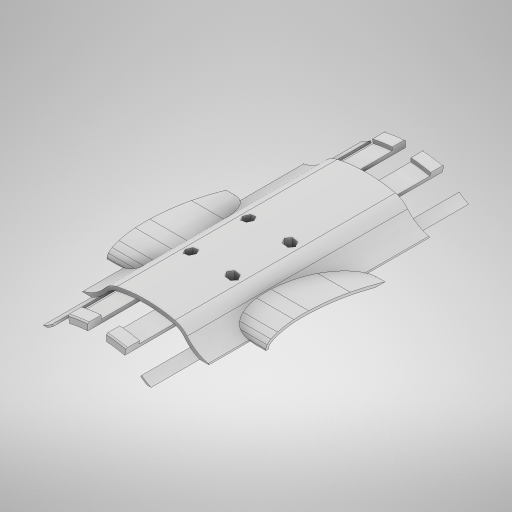
# Autodesk Inventor part: ENCASTRE_FUSELAJE
Saved by Autodesk Inventor 2023 (Build 270158000, 158)
## iProperties
Created: 2023-05-19
Part Number: ENCASTRE_FUSELAJE
Material: Genérico
Document SubType Name: Modeling
Designer: brand
Density: 1 g/cm^3
Appearance: Valor por defecto
Author: brand
Autodesk Inventor part; units mm, degrees
ref_plane "XZ Plane" through (0, 0, 0) normal (0, 1, 0) x (-1, 0, 0)
ref_plane "XY Plane" through (0, 0, 0) normal (0, 0, 1) x (1, 0, 0)
sketch "Boceto1" plane through (0, 0, 0) normal (0, 0, 1) x (1, 0, 0)
  line L0 (-27.5, 0) -> (27.5, 0) construction
  arc A0 (33, 24.3875) -> (-33, 24.3875) centre (0, -121.9375) ccw
  arc A1 (-33, -24.3875) -> (33, -24.3875) centre (0, 121.9375) ccw
  arc A2 (-70.9258, 0.9771) -> (-46.9085, 15.7579) centre (-80, 42.625) ccw
  arc A3 (-46.9085, -15.7579) -> (-70.9258, -0.9771) centre (-80, -42.625) ccw
  line L1 (0, 28.0625) -> (0, -28.0625) construction
  arc A4 (46.9085, 15.7579) -> (70.9258, 0.9771) centre (80, 42.625) ccw
  arc A5 (70.9258, -0.9771) -> (46.9085, -15.7579) centre (80, -42.625) ccw
  arc A6 (-33, 24.3875) -> (-46.9085, 15.7579) centre (-27.5, 0) ccw
  arc A7 (-46.9085, -15.7579) -> (-33, -24.3875) centre (-27.5, 0) ccw
  arc A8 (33, -24.3875) -> (46.9085, -15.7579) centre (27.5, 0) ccw
  arc A9 (46.9085, 15.7579) -> (33, 24.3875) centre (27.5, 0) ccw
  arc A10 (32.12, 20.4855) -> (-32.12, 20.4855) centre (0, -121.9375) ccw
  arc A11 (43.8031, 13.2366) -> (32.12, 20.4855) centre (27.5, 0) ccw
  arc A12 (43.8031, 13.2366) -> (61.1056, 0) centre (80, 42.625) ccw
  arc A13 (61.1056, 0) -> (43.8031, -13.2366) centre (80, -42.625) ccw
  arc A14 (32.12, -20.4855) -> (43.8031, -13.2366) centre (27.5, 0) ccw
  arc A15 (-32.12, -20.4855) -> (32.12, -20.4855) centre (0, 121.9375) ccw
  arc A16 (-43.8031, -13.2366) -> (-32.12, -20.4855) centre (-27.5, 0) ccw
  arc A17 (-43.8031, -13.2366) -> (-61.1056, 0) centre (-80, -42.625) ccw
  arc A18 (-61.1056, 0) -> (-43.8031, 13.2366) centre (-80, 42.625) ccw
  arc A19 (-32.12, 20.4855) -> (-43.8031, 13.2366) centre (-27.5, 0) ccw
  arc A20 (-70.9258, 0.9771) -> (-70.9258, -0.9771) centre (-70.7129, 0) ccw
  arc A21 (70.9258, -0.9771) -> (70.9258, 0.9771) centre (70.7129, 0) ccw
  point P0 (0, 0)
  point P1 (0, 0)
  point P2 (0, 0)
  dimension "d0" = 300
  dimension "d1" = 55
  dimension "d2" = 80
  dimension "d3" = 80
  dimension "d4" = 4
  dimension "d5" = 1
  constraints: 46 point on circle, 22 centre point, 6 tangent, 5 symmetric about line, 4 end point, 2 horizontal alignment, 1 coincident, 1 equal radius, 1 horizontal, 1 midpoint, 9 other
  measures "d0" diameter of A0
  measures "d1" distance of L0.start L0.end
  measures "d2" horizontal distance of point (0, 0) A18.centre
  measures "d3" horizontal distance of point (0, 0) A17.centre
  measures "d4" radial gap between concentric circles of A0 A10
  measures "d5" radius of A20
extrude "Extrusión1" add sketch "Boceto1" against normal blind 170
sketch "Boceto2" plane through (0, 0, 0) normal (1, 0, 0) x (0, 1, 0)
  arc A0 (-6.4315, -149.3718) -> (5.8247, -101.1329) centre (-420.6839, -18.445) ccw
  arc A1 (5.8247, -101.1329) -> (11.1529, -54.4749) centre (-297.3284, -42.881) ccw
  arc A2 (11.1529, -54.4749) -> (10.9145, -38.2426) centre (-144.1615, -48.6381) ccw
  arc A3 (10.9145, -38.2426) -> (7.8362, -20.5745) centre (-74.6379, -44.046) ccw
  arc A4 (7.8362, -20.5745) -> (5.0303, -13.6138) centre (-27.6939, -30.851) ccw
  arc A5 (5.0303, -13.6138) -> (2.575, -10.4857) centre (-4.0493, -18.2127) ccw
  arc A6 (2.575, -10.4857) -> (1.0803, -9.8637) centre (0.7767, -12.7005) ccw
  arc A7 (1.0803, -9.8637) -> (0.0741, -10.1303) centre (1.0883, -11.9261) ccw
  arc A8 (0.0741, -10.1303) -> (-1.6628, -12.1788) centre (2.0349, -13.5535) ccw
  arc A9 (-1.6628, -12.1788) -> (-2.3399, -14.3359) centre (17.2896, -19.3122) ccw
  arc A10 (-2.3399, -14.3359) -> (-3.2686, -18.7673) centre (27.4031, -22.8823) ccw
  arc A11 (-3.2686, -18.7673) -> (-3.7812, -23.8522) centre (82.0127, -29.9326) ccw
  arc A12 (-3.7812, -23.8522) -> (-4.3081, -39.7592) centre (210.5666, -38.9149) ccw
  line L0 (-4.3081, -39.7592) -> (-4.2703, -45.447)
  line L1 (-4.2703, -45.447) -> (-4.0474, -59.6695)
  arc A13 (-4.2226, -74.4673) -> (-4.0474, -59.6695) centre (-320.6036, -63.321) ccw
  arc A14 (-4.9188, -90.3853) -> (-4.2226, -74.4673) centre (-890.267, -43.6885) ccw
  line L2 (-4.9188, -90.3853) -> (-5.6302, -104.0213)
  arc A15 (-5.6302, -104.0213) -> (-6.0563, -116.5268) centre (482.8669, -126.9256) ccw
  arc A16 (-6.0563, -116.5268) -> (-6.3146, -149.378) centre (962.6143, -140.5688) ccw
  line L3 (-6.3146, -149.378) -> (-6.4315, -149.3718)
  line L4 (0, 0) -> (0, -170) projected
  arc A17 (-4.5792, -23.7958) -> (-5.1081, -39.7634) centre (210.5666, -38.9149) ccw
  arc A18 (-4.0616, -18.6622) -> (-4.5792, -23.7958) centre (82.0127, -29.9326) ccw
  arc A19 (-3.1122, -14.127) -> (-4.0616, -18.6622) centre (27.4031, -22.8823) ccw
  arc A20 (-2.4121, -11.8984) -> (-3.1122, -14.127) centre (17.2896, -19.3122) ccw
  arc A21 (-0.3215, -9.435) -> (-2.4121, -11.8984) centre (2.0349, -13.5535) ccw
  arc A22 (1.1223, -9.0639) -> (-0.3215, -9.435) centre (1.0883, -11.9261) ccw
  arc A23 (3.0879, -9.8716) -> (1.1223, -9.0639) centre (0.7767, -12.7005) ccw
  arc A24 (5.741, -13.2466) -> (3.0879, -9.8716) centre (-4.0493, -18.2127) ccw
  arc A25 (8.6051, -20.3539) -> (5.741, -13.2466) centre (-27.6939, -30.851) ccw
  arc A26 (11.7126, -38.1888) -> (8.6051, -20.3539) centre (-74.6379, -44.046) ccw
  arc A27 (11.9522, -54.5073) -> (11.7126, -38.1888) centre (-144.1615, -48.6381) ccw
  arc A28 (6.6102, -101.2845) -> (11.9522, -54.5073) centre (-297.3284, -42.881) ccw
  arc A29 (-5.8557, -150.2031) -> (6.6102, -101.2845) centre (-420.6839, -18.445) ccw
  line L5 (-5.8557, -150.2031) -> (-7.1074, -150.1375)
  arc A30 (-6.8561, -116.5083) -> (-7.1074, -150.1375) centre (962.6143, -140.5688) ccw
  arc A31 (-6.4292, -103.9817) -> (-6.8561, -116.5083) centre (482.8669, -126.9256) ccw
  line L6 (-6.4292, -103.9817) -> (-5.7177, -90.3434)
  arc A32 (-5.7177, -90.3434) -> (-5.0221, -74.4394) centre (-890.267, -43.6885) ccw
  arc A33 (-5.0221, -74.4394) -> (-4.8473, -59.6804) centre (-320.6036, -63.321) ccw
  line L7 (-4.8473, -59.6804) -> (-5.0703, -45.4559)
  line L8 (-5.0703, -45.4559) -> (-5.1081, -39.7634)
  line L9 (1.1223, -9.0639) -> (-24.0625, -9.0639) construction
  line L10 (-24.0625, -170) -> (-24.0625, 0) projected
  line L11 (-5.9636, -150.0472) -> (-24.0625, -150.0472) construction
  circle A34 centre (-336.4534, -54.4805) radius 340 construction
  line L12 (-24.0625, -6.0639) -> (24.3875, -6.0639)
  line L13 (24.3875, 0) -> (24.3875, -170) projected
  line L14 (-24.0625, -153.0472) -> (24.3875, -153.0472)
  circle A35 centre (1.7519, -16.7828) radius 2.25
  circle A36 centre (3.3626, -54.9049) radius 4.25
  circle A37 centre (-1.8171, -114.7492) radius 2.25
  point P0 (0, -10)
  dimension "d8" = 10
  dimension "d9" = 0.8
  dimension "d11" = 680
  dimension "d12" = 336.4534
  dimension "d13" = 54.4805
  dimension "d14" = 3
  dimension "d15" = 3
  dimension "d16" = 150.0472
  dimension "d19" = 4.5
  dimension "d20" = 8.5
  dimension "d21" = 4.5
  dimension "d22" = 16.7828
  dimension "d23" = 1.7519
  dimension "d24" = 54.9049
  dimension "d25" = 3.3626
  dimension "d26" = 114.7492
  dimension "d27" = 1.8171
  constraints: 68 point on circle, 38 centre point, 24 end point, 6 point on line, 3 horizontal, 1 perpendicular, 20 other
  measures "d8" distance of L4.start point (0, -10)
  measures "d9" radial gap between concentric circles of A12 A17
  measures "d11" diameter of A34
  measures "d12" horizontal distance of A34.centre L4.start
  measures "d13" vertical distance of A34.centre L4.start
  measures "d14" distance between parallel lines of L12 L9
  measures "d15" distance between parallel lines of L14 L11
  measures "d16" distance from line of L11 L4.start
  measures "d19" diameter of A35
  measures "d20" diameter of A36
  measures "d21" diameter of A37
  measures "d22" vertical distance of A35.centre L4.start
  measures "d23" horizontal distance of A35.centre L4.start
  measures "d24" vertical distance of A36.centre L4.start
  measures "d25" horizontal distance of A36.centre L4.start
  measures "d26" vertical distance of A37.centre L4.start
  measures "d27" horizontal distance of A37.centre L4.start
extrude "Extrusión2" add sketch "Boceto2" along normal mid plane 13 contours A29 A28 A27 A26 A25 A24 A23 A22 L4 L12 L13 L14 | L4 L14 L10 L12 A22 A21 A20 A19 A18 A17 L8 L7 A33 A32 L6 A31 A30 L5 A29
sketch "Boceto3" plane through (6.5, 0, 0) normal (1, 0, 0) x (0, 0, -1)
  line L0 (153.0472, 23.9178) -> (6.0639, 23.9178) projected
  line L1 (6.0639, -23.9178) -> (153.0472, -23.9178) projected
  line L2 (6.0639, -23.9178) -> (6.0639, 23.9178) projected
  line L3 (153.0472, 23.9178) -> (153.0472, -23.9178) projected
  circle A0 centre (16.783, 1.752) radius 4
  circle A1 centre (54.905, 3.363) radius 5.25
  circle A2 centre (114.749, -1.817) radius 4
  point P0 (0, 0)
  dimension "d28" = 8
  dimension "d29" = 10.5
  dimension "d30" = 8
  dimension "d31" = 16.783
  dimension "d32" = 1.752
  dimension "d33" = 3.363
  dimension "d34" = 54.905
  dimension "d35" = 114.749
  dimension "d36" = 1.817
  constraints: 3 centre point
  measures "d28" diameter of A0
  measures "d29" diameter of A1
  measures "d30" diameter of A2
  measures "d31" horizontal distance of point (0, 0) A0.centre
  measures "d32" vertical distance of point (0, 0) A0.centre
  measures "d33" vertical distance of point (0, 0) A1.centre
  measures "d34" horizontal distance of point (0, 0) A1.centre
  measures "d35" horizontal distance of point (0, 0) A2.centre
  measures "d36" vertical distance of point (0, 0) A2.centre
extrude "Extrusión3" add sketch "Boceto3" along normal blind 4
mirror "Simetría1" about plane through (0, 0, 0) normal (1, 0, 0) of "Extrusión3"
sketch "Boceto4" plane through (0, 0, 0) normal (1, 0, 0) x (0, 1, 0)
  circle A0 centre (1.752, -16.783) radius 4 projected
  circle A1 centre (3.363, -54.905) radius 5.25 projected
  circle A2 centre (-1.817, -114.749) radius 4 projected
  point P0 (0, 0)
extrude "Extrusión4" cut sketch "Boceto4" along normal through all both and the other way through all
sketch "Boceto5" plane through (0, 0, 0) normal (0, 1, 0) x (-1, 0, 0)
  circle A0 centre (-23.62, -99.8876) radius 8.5
  line L0 (32.12, -170) -> (-32.12, -170) projected
  line L1 (-33, -170) -> (33, -170) projected
  line L2 (0, -170) -> (0, 0)
  line L3 (10.5, -153.0472) -> (-10.5, -153.0472) projected
  line L4 (-10.5, -153.0472) -> (-10.5, -6.0639) projected
  line L5 (-10.5, -6.0639) -> (10.5, -6.0639) projected
  line L6 (10.5, -6.0639) -> (10.5, -153.0472) projected
  line L7 (-32.12, 0) -> (32.12, 0) projected
  line L8 (-32.12, 0) -> (-32.12, -170) projected
  line L9 (32.12, -170) -> (-32.12, -170) projected
  line L10 (32.12, 0) -> (32.12, -170) projected
  circle A1 centre (-23.62, -34.8116) radius 8.5
  circle A2 centre (23.62, -99.8876) radius 8.5
  circle A3 centre (23.62, -34.8116) radius 8.5
  circle A4 centre (-23.62, -99.8876) radius 3.25
  circle A5 centre (-23.62, -34.8116) radius 3.25
  circle A6 centre (23.62, -99.8876) radius 3.25
  circle A7 centre (23.62, -34.8116) radius 3.25
  dimension "d41" = 17
  dimension "d42" = 6.5
  dimension "d43" = 6.5
  constraints: 8 centre point, 4 symmetric about line, 2 coincident, 2 end point, 2 tangent, 1 equal radius, 1 midpoint, 1 vertical, 4 other
  measures "d41" diameter of A0
  measures "d42" diameter of A4
  measures "d43" diameter of A5
extrude "Extrusión5" add sketch "Boceto5" along normal mid plane 20 contours A0 | A1 | A2 | A3
sketch "Boceto6" plane through (23.62, 10, -34.8116) normal (0, 1, 0) x (1, 0, 0)
  circle A0 centre (0, 0) radius 3.25 projected
  line L0 (-3.1754, 5.5) -> (3.1754, 5.5)
  line L1 (3.1754, 5.5) -> (6.3509, 0)
  line L2 (6.3509, 0) -> (3.1754, -5.5)
  line L3 (3.1754, -5.5) -> (-3.1754, -5.5)
  line L4 (-3.1754, -5.5) -> (-6.3509, 0)
  line L5 (-6.3509, 0) -> (-3.1754, 5.5)
  circle A1 centre (0, 0) radius 10.5
  line L6 (-23.62, -34.8116) -> (-23.62, 135.1884)
  line L7 (9.38, 135.1884) -> (-56.62, 135.1884) projected
  circle A2 centre (0, 65.076) radius 3.25 projected
  line L8 (0, 65.076) -> (0, 0)
  line L9 (0, 32.538) -> (-50.0066, 32.538)
  circle A3 centre (0, 65.076) radius 3.25
  line L10 (-3.1754, 59.576) -> (3.1754, 59.576)
  line L11 (3.1754, 59.576) -> (6.3509, 65.076)
  line L12 (6.3509, 65.076) -> (3.1754, 70.576)
  line L13 (3.1754, 70.576) -> (-3.1754, 70.576)
  line L14 (-3.1754, 70.576) -> (-6.3509, 65.076)
  line L15 (-6.3509, 65.076) -> (-3.1754, 59.576)
  circle A4 centre (0, 65.076) radius 10.5
  circle A5 centre (-47.24, 0) radius 3.25
  line L16 (-44.0646, 5.5) -> (-50.4154, 5.5)
  line L17 (-50.4154, 5.5) -> (-53.5909, 0)
  line L18 (-53.5909, 0) -> (-50.4154, -5.5)
  line L19 (-50.4154, -5.5) -> (-44.0646, -5.5)
  line L20 (-44.0646, -5.5) -> (-40.8891, 0)
  line L21 (-40.8891, 0) -> (-44.0646, 5.5)
  circle A6 centre (-47.24, 0) radius 10.5
  circle A7 centre (-47.24, 65.076) radius 3.25
  line L22 (-47.24, 65.076) -> (-47.24, 0)
  line L23 (-50.4154, 59.576) -> (-53.5909, 65.076)
  line L24 (-40.8891, 65.076) -> (-44.0646, 59.576)
  circle A8 centre (-47.24, 65.076) radius 3.25
  line L25 (-53.5909, 65.076) -> (-50.4154, 70.576)
  line L26 (-50.4154, 70.576) -> (-44.0646, 70.576)
  line L27 (-44.0646, 70.576) -> (-40.8891, 65.076)
  circle A9 centre (-47.24, 65.076) radius 10.5
  line L28 (-44.0646, 59.576) -> (-50.4154, 59.576)
  point P0 (0, 5.5)
  point P1 (0, 59.576)
  point P2 (-47.24, 5.5)
  point P3 (-47.24, 32.538)
  point P4 (-47.24, 59.576)
  dimension "d46" = 11
  dimension "d47" = 11
  dimension "d48" = 11
  dimension "d49" = 120
  dimension "d50" = 120
  dimension "d51" = 21
  constraints: 56 end point, 27 symmetric about line, 8 centre point, 4 coincident, 3 midpoint, 3 parallel, 2 horizontal, 1 equal length, 1 horizontal alignment, 1 vertical, 1 vertical alignment, 7 other
  measures "d46" distance between parallel lines of L3 L0
  measures "d47" distance between parallel lines of L4 L1
  measures "d48" distance between parallel lines of L5 L2
  measures "d49" angle of L5 L0
  measures "d50" angle of L2 L1
  measures "d51" diameter of A1
extrude "Extrusión6" add sketch "Boceto6" along normal through all contours A1 | A4 | A6 | A9
sketch "Boceto7" plane through (-23.62, 10, -34.8116) normal (0, -1, 0) x (1, 0, 0)
  line L0 (-6.3509, 0) -> (-3.1754, -5.5) projected
  line L1 (-3.1754, -5.5) -> (3.1754, -5.5) projected
  line L2 (3.1754, -5.5) -> (6.3509, 0) projected
  line L3 (6.3509, 0) -> (3.1754, 5.5) projected
  line L4 (3.1754, 5.5) -> (-3.1754, 5.5) projected
  line L5 (-3.1754, 5.5) -> (-6.3509, 0) projected
  line L6 (40.8891, 0) -> (44.0646, -5.5) projected
  line L7 (44.0646, -5.5) -> (50.4154, -5.5) projected
  line L8 (50.4154, -5.5) -> (53.5909, 0) projected
  line L9 (53.5909, 0) -> (50.4154, 5.5) projected
  line L10 (50.4154, 5.5) -> (44.0646, 5.5) projected
  line L11 (44.0646, 5.5) -> (40.8891, 0) projected
  line L12 (53.5909, -65.076) -> (50.4154, -59.576) projected
  line L13 (50.4154, -59.576) -> (44.0646, -59.576) projected
  line L14 (44.0646, -59.576) -> (40.8891, -65.076) projected
  line L15 (40.8891, -65.076) -> (44.0646, -70.576) projected
  line L16 (44.0646, -70.576) -> (50.4154, -70.576) projected
  line L17 (50.4154, -70.576) -> (53.5909, -65.076) projected
  line L18 (6.3509, -65.076) -> (3.1754, -59.576) projected
  line L19 (3.1754, -59.576) -> (-3.1754, -59.576) projected
  line L20 (-3.1754, -59.576) -> (-6.3509, -65.076) projected
  line L21 (-6.3509, -65.076) -> (-3.1754, -70.576) projected
  line L22 (-3.1754, -70.576) -> (3.1754, -70.576) projected
  line L23 (3.1754, -70.576) -> (6.3509, -65.076) projected
  point P0 (23.62, 34.8116)
extrude "Extrusión7" cut sketch "Boceto7" against normal through all
sketch "Boceto8" plane through (-23.62, -10, -34.8116) normal (0, -1, 0) x (1, 0, 0)
  circle A0 centre (0, 0) radius 10.5 projected
  circle A1 centre (0, 0) radius 8.5 projected
  circle A2 centre (47.24, 0) radius 10.5 projected
  circle A3 centre (47.24, 0) radius 8.5 projected
  circle A4 centre (47.24, -65.076) radius 10.5 projected
  circle A5 centre (47.24, -65.076) radius 8.5 projected
  circle A6 centre (0, -65.076) radius 10.5 projected
  circle A7 centre (0, -65.076) radius 8.5 projected
  point P0 (23.62, 34.8116)
extrude "Extrusión8" add sketch "Boceto8" against normal blind 5
sketch "Boceto9" plane through (-23.62, -10, -34.8116) normal (0, -1, 0) x (1, 0, 0)
  circle A0 centre (0, 0) radius 8.5 projected
  circle A1 centre (47.24, 0) radius 8.5 projected
  circle A2 centre (47.24, -65.076) radius 8.5 projected
  circle A3 centre (0, -65.076) radius 8.5 projected
  point P0 (23.62, 34.8116)
extrude "Extrusión9" cut sketch "Boceto9" along normal through all
sketch "Boceto10" plane through (-23.62, -10, -34.8116) normal (0, -1, 0) x (1, 0, 0)
  circle A0 centre (0, 0) radius 10.5 projected
  circle A1 centre (47.24, 0) radius 10.5 projected
  circle A2 centre (0, -65.076) radius 10.5 projected
  circle A3 centre (47.24, -65.076) radius 10.5 projected
  circle A4 centre (0, 0) radius 8.5 projected
  circle A5 centre (47.24, 0) radius 10.5 projected
  circle A6 centre (47.24, 0) radius 8.5 projected
  circle A7 centre (47.24, -65.076) radius 10.5 projected
  circle A8 centre (47.24, -65.076) radius 8.5 projected
  circle A9 centre (0, -65.076) radius 10.5 projected
  circle A10 centre (0, -65.076) radius 8.5 projected
  point P0 (23.62, 34.8116)
extrude "Extrusión10" add sketch "Boceto10" along normal through all
sketch "Boceto11" plane through (0, 0, 0) normal (0, 0, 1) x (1, 0, 0)
  arc A0 (10.5, 23.6845) -> (-10.5, 23.6845) centre (0, -121.9375) ccw projected
  line L0 (-10.5, 23.6845) -> (-10.5, -23.6845) projected
  arc A1 (-10.5, -23.6845) -> (10.5, -23.6845) centre (0, 121.9375) ccw projected
  line L1 (10.5, 23.6845) -> (10.5, -23.6845) projected
  line L2 (-10.5, 0) -> (-77.0735, 0)
  line L3 (-15.12, -5) -> (-15.12, 10) projected
  line L4 (-77.0735, 0) -> (-77.0735, -40.4156)
  line L5 (-77.0735, -40.4156) -> (86.7734, -40.4156)
  line L6 (86.7734, -40.4156) -> (86.7734, 0)
  line L7 (86.7734, 0) -> (10.5, 0)
  line L8 (10.5, -23.6845) -> (10.5, 23.6845) projected
  point P0 (0, 0)
  point P1 (10.5, 0)
  constraints: 10 end point, 4 perpendicular, 2 midpoint, 1 point on line
extrude "Extrusión11" cut sketch "Boceto11" against normal through all contours L7 L6 L5 L4 L2 L0 A1 L1
sketch "Boceto12" plane through (10.5, 0, 0) normal (1, 0, 0) x (0, 0, -1)
  circle A0 centre (54.481, -336.453) radius 340
  point P0 (0, 0)
  dimension "d64" = 680
  dimension "d65" = 336.453
  dimension "d66" = 54.481
  constraints: 1 centre point
  measures "d64" diameter of A0
  measures "d65" vertical distance of point (0, 0) A0.centre
  measures "d66" horizontal distance of point (0, 0) A0.centre
extrude "Extrusión12" cut sketch "Boceto12" against normal up to surface (21 mm away)
ref_plane "Plano de trabajo1" through (90, 0, 0) normal (1, 0, 0) x (0, 1, 0)
sketch "Boceto13" plane through (90, 0, 0) normal (1, 0, 0) x (0, 1, 0)
  arc A0 (3.5128, -49.6571) -> (1.8728, -20.7812) centre (-336.453, -54.481) ccw projected
  arc A1 (3.4997, -60.1532) -> (3.5128, -49.6571) centre (3.363, -54.905) ccw projected
  arc A2 (-1.1507, -110.8049) -> (3.4997, -60.1532) centre (-336.453, -54.481) ccw projected
  arc A3 (-2.5686, -118.6777) -> (-1.1507, -110.8049) centre (-1.817, -114.749) ccw projected
  arc A4 (-7.1535, -139.1087) -> (-2.5686, -118.6777) centre (-336.453, -54.481) ccw projected
  arc A5 (-7.1535, -139.1087) -> (-7.1074, -150.1375) centre (962.6143, -140.5688) ccw projected
  line L0 (-7.1074, -150.1375) -> (-5.8557, -150.2031) projected
  arc A6 (-5.8557, -150.2031) -> (6.6102, -101.2845) centre (-420.6839, -18.445) ccw projected
  arc A7 (6.6102, -101.2845) -> (11.9522, -54.5073) centre (-297.3284, -42.881) ccw projected
  arc A8 (11.9522, -54.5073) -> (11.7126, -38.1888) centre (-144.1615, -48.6381) ccw projected
  arc A9 (11.7126, -38.1888) -> (8.6051, -20.3539) centre (-74.6379, -44.046) ccw projected
  arc A10 (8.6051, -20.3539) -> (5.741, -13.2466) centre (-27.6939, -30.851) ccw projected
  arc A11 (5.741, -13.2466) -> (3.0879, -9.8716) centre (-4.0493, -18.2127) ccw projected
  arc A12 (3.0879, -9.8716) -> (1.1223, -9.0639) centre (0.7767, -12.7005) ccw projected
  arc A13 (1.1223, -9.0639) -> (0.5079, -9.1232) centre (1.0883, -11.9261) ccw projected
  arc A14 (0.9894, -12.8564) -> (0.5079, -9.1232) centre (-336.453, -54.481) ccw projected
  arc A15 (1.8728, -20.7812) -> (0.9894, -12.8564) centre (1.752, -16.783) ccw projected
  arc A16 (9.5559, -101.853) -> (14.9501, -54.6188) centre (-297.3284, -42.881) ccw
  arc A17 (-3.7044, -153.32) -> (9.5559, -101.853) centre (-420.6839, -18.445) ccw
  line L1 (-3.7044, -153.32) -> (-10.0754, -152.9861)
  arc A18 (-10.1529, -138.726) -> (-10.0754, -152.9861) centre (962.6143, -140.5688) ccw
  arc A19 (-10.1529, -138.726) -> (-4.401, -112.0178) centre (-336.453, -54.481) ccw
  arc A20 (-4.401, -112.0178) -> (0.5257, -50.6918) centre (-336.453, -54.481) ccw
  arc A21 (0.5257, -50.6918) -> (-1.7792, -14.9536) centre (-336.453, -54.481) ccw
  arc A22 (-1.7792, -14.9536) -> (-2.7452, -7.4907) centre (-336.453, -54.481) ccw
  arc A23 (1.2859, -6.067) -> (-2.7452, -7.4907) centre (1.0883, -11.9261) ccw
  arc A24 (5.0147, -7.572) -> (1.2859, -6.067) centre (0.7767, -12.7005) ccw
  arc A25 (8.4058, -11.8683) -> (5.0147, -7.572) centre (-4.0493, -18.2127) ccw
  arc A26 (11.4888, -19.5266) -> (8.4058, -11.8683) centre (-27.6939, -30.851) ccw
  arc A27 (14.7058, -37.987) -> (11.4888, -19.5266) centre (-74.6379, -44.046) ccw
  arc A28 (14.9501, -54.6188) -> (14.7058, -37.987) centre (-144.1615, -48.6381) ccw
  line L2 (0, -58.9365) -> (0, -111.1855) projected
  line L3 (0, -58.9365) -> (0, -111.1855) projected
  line L4 (0, -58.9365) -> (0, 0)
  line L5 (0, -118.3125) -> (0, -170) projected
  line L6 (0, 0) -> (0, -170)
  circle A29 centre (1.752, -16.783) radius 4
  circle A30 centre (3.363, -54.905) radius 5.25
  circle A31 centre (-1.817, -114.749) radius 4
  line L7 (0.5079, -9.1232) -> (0, -9.3838)
  line L8 (0, 0) -> (0, -13.1871) projected
  point P0 (0, -103.4645)
  point P1 (3.4997, -60.1532)
  point P2 (3.5128, -49.6571)
  point P3 (1.8728, -20.7812)
  point P4 (0, -20.3789)
  point P5 (0, -50.8735)
  point P6 (0, -130.1039)
  point P7 (0, -141.2791)
  point P8 (0, -6.1656)
  point P9 (0, -13.1871)
  point P10 (0.9894, -12.8564)
  point P11 (0, -9.3838)
  dimension "d70" = 3
  constraints: 26 point on circle, 15 centre point, 8 end point, 3 coincident, 2 concentric, 1 collinear, 1 point on line, 16 other
  measures "d70" radial gap between concentric circles of A7 A16
extrude "Extrusión13" add sketch "Boceto13" against normal up to surface contours L7 L4 A23 A24 A25 A26 A27 A28 A16 A17 L5 A6 A7 A8 A9 A10 A11 A12 A13 round surface about axis through (80, 42.625, 0) along (0, 0, -1) radius 42.625 far side no
mirror "Simetría3" about plane through (0, 0, 0) normal (1, 0, 0) of "Extrusión13"
sketch "Boceto16" plane through (-6.5, -420.6839, -18.445) normal (1, 0, 0) x (0, -0.2469378, -0.9690313)
  arc A0 (-74.5046, 418.7673) -> (-102.0813, 410.0475) centre (14.1202, 90.521) ccw projected
  arc A1 (-64.3304, 421.3465) -> (-74.5046, 418.7673) centre (-69.3823, 419.9181) ccw projected
  arc A2 (-14.0989, 429.3479) -> (-64.3304, 421.3465) centre (14.1202, 90.521) ccw projected
  arc A3 (-6.1198, 429.918) -> (-14.0989, 429.3479) centre (-10.1124, 429.6762) ccw projected
  arc A4 (29.2806, 430.1828) -> (-6.1198, 429.918) centre (14.1202, 90.521) ccw projected
  line L0 (29.2806, 430.1828) -> (20.7025, 463.8452) projected
  line L1 (-121.729, 427.5495) -> (20.7025, 463.8452) projected
  line L2 (-121.729, 427.5495) -> (-115.9006, 404.6779) projected
  arc A5 (-109.5426, 407.2346) -> (-115.9006, 404.6779) centre (14.1202, 90.521) ccw projected
  arc A6 (-102.0813, 410.0475) -> (-109.5426, 407.2346) centre (-105.9259, 408.9432) ccw projected
  arc A7 (14.8107, 430.5203) -> (25.4865, 433.2884) centre (-223.2468, 1370.6162) ccw projected
  line L3 (25.241, 434.5176) -> (25.4865, 433.2884) projected
  line L4 (25.4865, 433.2884) -> (26.0814, 430.3105)
  point P0 (-121.7565, 403.1011)
  constraints: 2 end point, 1 collinear, 1 point on circle
extrude "Extrusión16" cut sketch "Boceto16" along normal up to surface (13 mm away) contours A7 L4 A4
sketch "Boceto17" plane through (0, 0, 0) normal (0, 0, 1) x (1, 0, 0)
  line L0 (61.1056, 0) -> (71.7129, 0) projected
  arc A0 (71.7129, 0) -> (70.9258, 0.9771) centre (70.7129, 0) ccw projected
  arc A1 (46.9085, 15.7579) -> (70.9258, 0.9771) centre (80, 42.625) ccw projected
  arc A2 (46.9085, 15.7579) -> (33, 24.3875) centre (27.5, 0) ccw projected
  arc A3 (33, 24.3875) -> (-33, 24.3875) centre (0, -121.9375) ccw projected
  arc A4 (-33, 24.3875) -> (-46.9085, 15.7579) centre (-27.5, 0) ccw projected
  arc A5 (-70.9258, 0.9771) -> (-46.9085, 15.7579) centre (-80, 42.625) ccw projected
  arc A6 (-70.9258, 0.9771) -> (-71.7129, 0) centre (-70.7129, 0) ccw projected
  line L1 (-71.7129, 0) -> (-61.1056, 0) projected
  arc A7 (-61.1056, 0) -> (-43.8031, 13.2366) centre (-80, 42.625) ccw projected
  arc A8 (-32.12, 20.4855) -> (-43.8031, 13.2366) centre (-27.5, 0) ccw projected
  arc A9 (32.12, 20.4855) -> (-32.12, 20.4855) centre (0, -121.9375) ccw projected
  arc A10 (43.8031, 13.2366) -> (32.12, 20.4855) centre (27.5, 0) ccw projected
  arc A11 (43.8031, 13.2366) -> (61.1056, 0) centre (80, 42.625) ccw projected
  point P0 (0, 0)
extrude "Extrusión17" add sketch "Boceto17" along normal blind 40
sketch "Boceto18" plane through (0, 0, -170) normal (0, 0, -1) x (-1, 0, 0)
  line L0 (61.1056, 0) -> (71.7129, 0) projected
  arc A0 (71.7129, 0) -> (70.9258, 0.9771) centre (70.7129, 0) ccw projected
  arc A1 (46.9085, 15.7579) -> (70.9258, 0.9771) centre (80, 42.625) ccw projected
  arc A2 (46.9085, 15.7579) -> (33, 24.3875) centre (27.5, 0) ccw projected
  arc A3 (33, 24.3875) -> (-33, 24.3875) centre (0, -121.9375) ccw projected
  arc A4 (-33, 24.3875) -> (-46.9085, 15.7579) centre (-27.5, 0) ccw projected
  arc A5 (-70.9258, 0.9771) -> (-46.9085, 15.7579) centre (-80, 42.625) ccw projected
  arc A6 (-70.9258, 0.9771) -> (-71.7129, 0) centre (-70.7129, 0) ccw projected
  line L1 (-71.7129, 0) -> (-61.1056, 0) projected
  arc A7 (-61.1056, 0) -> (-43.8031, 13.2366) centre (-80, 42.625) ccw projected
  arc A8 (-32.12, 20.4855) -> (-43.8031, 13.2366) centre (-27.5, 0) ccw projected
  arc A9 (32.12, 20.4855) -> (-32.12, 20.4855) centre (0, -121.9375) ccw projected
  arc A10 (43.8031, 13.2366) -> (32.12, 20.4855) centre (27.5, 0) ccw projected
  arc A11 (43.8031, 13.2366) -> (61.1056, 0) centre (80, 42.625) ccw projected
  point P0 (0, 0)
extrude "Extrusión18" add sketch "Boceto18" along normal blind 40
sketch "Boceto19" plane through (0, 0, 40) normal (0, 0, 1) x (1, 0, 0)
  line L0 (61.1056, 0) -> (71.7129, 0) projected
  arc A0 (71.7129, 0) -> (70.9258, 0.9771) centre (70.7129, 0) ccw projected
  arc A1 (46.9085, 15.7579) -> (70.9258, 0.9771) centre (80, 42.625) ccw projected
  arc A2 (46.9085, 15.7579) -> (33, 24.3875) centre (27.5, 0) ccw projected
  arc A3 (33, 24.3875) -> (-33, 24.3875) centre (0, -121.9375) ccw projected
  arc A4 (-33, 24.3875) -> (-46.9085, 15.7579) centre (-27.5, 0) ccw projected
  arc A5 (-70.9258, 0.9771) -> (-46.9085, 15.7579) centre (-80, 42.625) ccw projected
  arc A6 (-70.9258, 0.9771) -> (-71.7129, 0) centre (-70.7129, 0) ccw projected
  line L1 (-71.7129, 0) -> (-61.1056, 0) projected
  arc A7 (-61.1056, 0) -> (-43.8031, 13.2366) centre (-80, 42.625) ccw projected
  arc A8 (-32.12, 20.4855) -> (-43.8031, 13.2366) centre (-27.5, 0) ccw projected
  arc A9 (32.12, 20.4855) -> (-32.12, 20.4855) centre (0, -121.9375) ccw projected
  arc A10 (43.8031, 13.2366) -> (32.12, 20.4855) centre (27.5, 0) ccw projected
  arc A11 (43.8031, 13.2366) -> (61.1056, 0) centre (80, 42.625) ccw projected
  arc A12 (-31.24, 16.5835) -> (-40.6978, 10.7153) centre (-27.5, 0) ccw
  arc A13 (-60.2769, -4) -> (-40.6978, 10.7153) centre (-80, 42.625) ccw
  line L2 (-60.2769, -4) -> (-73.7129, -4)
  arc A14 (-71.7773, 4.8854) -> (-73.7129, -4) centre (-70.7129, 0) ccw
  arc A15 (-71.7773, 4.8854) -> (-50.0139, 18.2791) centre (-80, 42.625) ccw
  arc A16 (-33.88, 28.2895) -> (-50.0139, 18.2791) centre (-27.5, 0) ccw
  arc A17 (33.88, 28.2895) -> (-33.88, 28.2895) centre (0, -121.9375) ccw
  arc A18 (50.0139, 18.2791) -> (33.88, 28.2895) centre (27.5, 0) ccw
  arc A19 (50.0139, 18.2791) -> (71.7773, 4.8854) centre (80, 42.625) ccw
  arc A20 (73.7129, -4) -> (71.7773, 4.8854) centre (70.7129, 0) ccw
  line L3 (73.7129, -4) -> (60.2769, -4)
  arc A21 (40.6978, 10.7153) -> (60.2769, -4) centre (80, 42.625) ccw
  arc A22 (40.6978, 10.7153) -> (31.24, 16.5835) centre (27.5, 0) ccw
  arc A23 (31.24, 16.5835) -> (-31.24, 16.5835) centre (0, -121.9375) ccw
  line L4 (-32.12, 20.4855) -> (-31.24, 16.5835)
  line L5 (-10.5, 23.6845) -> (-10.5, 0.082) projected
  line L6 (-10.5, 23.6845) -> (-10.5, 19.6738)
  line L7 (32.12, 20.4855) -> (31.24, 16.5835)
  arc A24 (10.5, 23.6845) -> (-10.5, 23.6845) centre (0, -121.9375) ccw projected
  line L8 (10.5, 23.6845) -> (10.5, 19.6738)
  line L9 (10.5, 23.6845) -> (10.5, 0.082) projected
  point P0 (0, 0)
  point P1 (-31.24, 16.5835)
  dimension "d83" = 4
  dimension "d95" = 31.24
  dimension "d96" = 31.24
  dimension "d97" = 32.12
  dimension "d98" = 32.12
  constraints: 27 point on circle, 12 centre point, 12 end point, 2 point on line, 13 other
  measures "d83" radial gap between concentric circles of A9 A23
  measures "d95" horizontal distance of A22.end point (0, 0)
  measures "d96" horizontal distance of A12.start point (0, 0)
  measures "d97" horizontal distance of point (0, 0) L4.start
  measures "d98" horizontal distance of point (0, 0) L7.start
extrude "Extrusión19" add sketch "Boceto19" against normal blind 20 contours L7 A23 L8 A9 | L5 A23 L4 A9
sketch "Boceto20" plane through (0, 0, 40) normal (0, 0, 1) x (1, 0, 0)
  arc A0 (-10.5, 23.6845) -> (-32.12, 20.4855) centre (0, -121.9375) ccw projected
  line L0 (61.1056, 0) -> (71.7129, 0) projected
  arc A1 (71.7129, 0) -> (70.9258, 0.9771) centre (70.7129, 0) ccw projected
  arc A2 (46.9085, 15.7579) -> (70.9258, 0.9771) centre (80, 42.625) ccw projected
  arc A3 (46.9085, 15.7579) -> (33, 24.3875) centre (27.5, 0) ccw projected
  arc A4 (33, 24.3875) -> (-33, 24.3875) centre (0, -121.9375) ccw projected
  arc A5 (-33, 24.3875) -> (-46.9085, 15.7579) centre (-27.5, 0) ccw projected
  arc A6 (-70.9258, 0.9771) -> (-46.9085, 15.7579) centre (-80, 42.625) ccw projected
  arc A7 (-70.9258, 0.9771) -> (-71.7129, 0) centre (-70.7129, 0) ccw projected
  line L1 (-71.7129, 0) -> (-61.1056, 0) projected
  arc A8 (-61.1056, 0) -> (-43.8031, 13.2366) centre (-80, 42.625) ccw projected
  arc A9 (-32.12, 20.4855) -> (-43.8031, 13.2366) centre (-27.5, 0) ccw projected
  line L2 (-32.12, 20.4855) -> (-31.24, 16.5835) projected
  arc A10 (-10.5, 19.6738) -> (-31.24, 16.5835) centre (0, -121.9375) ccw projected
  line L3 (-10.5, 19.6738) -> (-10.5, 23.6845) projected
  arc A11 (10.5, 23.6845) -> (-10.5, 23.6845) centre (0, -121.9375) ccw projected
  line L4 (10.5, 23.6845) -> (10.5, 19.6738) projected
  arc A12 (31.24, 16.5835) -> (10.5, 19.6738) centre (0, -121.9375) ccw projected
  line L5 (31.24, 16.5835) -> (32.12, 20.4855) projected
  arc A13 (43.8031, 13.2366) -> (32.12, 20.4855) centre (27.5, 0) ccw projected
  arc A14 (43.8031, 13.2366) -> (61.1056, 0) centre (80, 42.625) ccw projected
  arc A15 (32.12, 20.4855) -> (10.5, 23.6845) centre (0, -121.9375) ccw projected
  arc A16 (8.8767, 21.7887) -> (-8.5, 21.8114) centre (0, -121.9375) ccw
  line L6 (-8.5, 21.8114) -> (-8.5, 17.8042)
  arc A17 (-8.5, 17.8042) -> (-32.7479, 14.1786) centre (0, -121.9375) ccw
  line L7 (-32.7479, 14.1786) -> (-33.6078, 17.9915)
  arc A18 (-33.6078, 17.9915) -> (-42.2505, 11.976) centre (-27.5, 0) ccw
  arc A19 (-60.6868, -2) -> (-42.2505, 11.976) centre (-80, 42.625) ccw
  line L8 (-60.6868, -2) -> (-72.949, -2)
  arc A20 (-71.3516, 2.9312) -> (-72.949, -2) centre (-70.7129, 0) ccw
  arc A21 (-71.3516, 2.9312) -> (-48.4612, 17.0185) centre (-80, 42.625) ccw
  arc A22 (-33.44, 26.3385) -> (-48.4612, 17.0185) centre (-27.5, 0) ccw
  arc A23 (33.44, 26.3385) -> (-33.44, 26.3385) centre (0, -121.9375) ccw
  arc A24 (48.4612, 17.0185) -> (33.44, 26.3385) centre (27.5, 0) ccw
  arc A25 (48.4612, 17.0185) -> (71.3516, 2.9312) centre (80, 42.625) ccw
  arc A26 (72.949, -2) -> (71.3516, 2.9312) centre (70.7129, 0) ccw
  line L9 (72.949, -2) -> (60.6868, -2)
  arc A27 (42.2505, 11.976) -> (60.6868, -2) centre (80, 42.625) ccw
  arc A28 (42.2505, 11.976) -> (31.68, 18.5345) centre (27.5, 0) ccw
  line L10 (-61.1056, 0) -> (-71.7129, 0) projected
  line L11 (-61.1056, 0) -> (-56.6013, 0)
  line L12 (-49.1982, 5) -> (-50.4651, 6.5476)
  arc A29 (-61.1056, 0) -> (-43.8031, 13.2366) centre (-80, 42.625) ccw projected
  line L13 (49.1982, 5) -> (50.4651, 6.5476)
  arc A30 (43.8031, 13.2366) -> (61.1056, 0) centre (80, 42.625) ccw projected
  line L14 (61.1056, 0) -> (56.6013, 0)
  point P0 (0, 0)
  point P1 (-10.5, 23.6845)
  point P2 (-32.12, 20.4855)
  point P3 (61.1056, 0)
  point P4 (-50.4651, 6.5476)
  dimension "d0" = 300
  dimension "d1" = 55
  dimension "d2" = 80
  dimension "d3" = 80
  dimension "d4" = 4
  dimension "d5" = 1
  dimension "d90" = 2
  dimension "d91" = 5
  dimension "d92" = 5
  constraints: 33 point on circle, 16 end point, 13 centre point, 2 line through centre, 1 collinear, 1 horizontal, 16 other
  measures "d90" radial gap between concentric circles of A8 A19
  measures "d91" distance from line of L11 L12.start
  measures "d92" distance from line of L0 L13.start
extrude "Extrusión20" add sketch "Boceto20" along normal blind 55 contours L3 A10 L2 A0 | A15 L5 A12 L4 | L12 A19 L11 A8 | A14 L14 A27 L13
sketch "Boceto21" plane through (0, 0, 95) normal (0, 0, 1) x (1, 0, 0)
  arc A0 (32.12, 20.4855) -> (10.5, 23.6845) centre (0, -121.9375) ccw projected
  arc A1 (43.8031, 13.2366) -> (32.12, 20.4855) centre (27.5, 0) ccw projected
  arc A2 (43.8031, 13.2366) -> (50.4651, 6.5476) centre (80, 42.625) ccw projected
  line L0 (61.1056, 0) -> (71.7129, 0) projected
  arc A3 (71.7129, 0) -> (70.9258, 0.9771) centre (70.7129, 0) ccw projected
  arc A4 (46.9085, 15.7579) -> (70.9258, 0.9771) centre (80, 42.625) ccw projected
  arc A5 (46.9085, 15.7579) -> (33, 24.3875) centre (27.5, 0) ccw projected
  arc A6 (33, 24.3875) -> (-33, 24.3875) centre (0, -121.9375) ccw projected
  arc A7 (-33, 24.3875) -> (-46.9085, 15.7579) centre (-27.5, 0) ccw projected
  arc A8 (-70.9258, 0.9771) -> (-46.9085, 15.7579) centre (-80, 42.625) ccw projected
  arc A9 (-70.9258, 0.9771) -> (-71.7129, 0) centre (-70.7129, 0) ccw projected
  line L1 (-71.7129, 0) -> (-61.1056, 0) projected
  arc A10 (-61.1056, 0) -> (-50.4651, 6.5476) centre (-80, 42.625) ccw projected
  arc A11 (-32.12, 20.4855) -> (-43.8031, 13.2366) centre (-27.5, 0) ccw projected
  arc A12 (-10.5, 23.6845) -> (-32.12, 20.4855) centre (0, -121.9375) ccw projected
  arc A13 (10.5, 23.6845) -> (-10.5, 23.6845) centre (0, -121.9375) ccw projected
  line L2 (-32.12, 20.4855) -> (-31.24, 16.5835) projected
  arc A14 (-10.5, 19.6738) -> (-31.24, 16.5835) centre (0, -121.9375) ccw projected
  line L3 (-10.5, 19.6738) -> (-10.5, 23.6845) projected
  arc A15 (-10.5, 23.6845) -> (-32.12, 20.4855) centre (0, -121.9375) ccw projected
  arc A16 (32.12, 20.4855) -> (10.5, 23.6845) centre (0, -121.9375) ccw projected
  line L4 (10.5, 23.6845) -> (10.5, 19.6738) projected
  arc A17 (31.24, 16.5835) -> (10.5, 19.6738) centre (0, -121.9375) ccw projected
  line L5 (31.24, 16.5835) -> (32.12, 20.4855) projected
  arc A18 (-10.5, 19.6738) -> (-31.24, 16.5835) centre (0, -121.9375) ccw projected
  line L6 (-31.24, 16.5835) -> (-33, 24.3875)
  line L7 (-31.24, 16.5835) -> (-32.12, 20.4855) projected
  line L8 (-10.5, 19.6738) -> (-10.5, 27.6946)
  line L9 (-10.5, 23.6845) -> (-10.5, 0.082) projected
  line L10 (10.5, 19.6738) -> (10.5, 27.6946)
  line L11 (32.12, 20.4855) -> (31.24, 16.5835) projected
  line L12 (31.24, 16.5835) -> (33, 24.3875)
  arc A19 (50.4651, 6.5476) -> (61.1056, 0) centre (80, 42.625) ccw projected
  arc A20 (-50.4651, 6.5476) -> (-43.8031, 13.2366) centre (-80, 42.625) ccw projected
  point P0 (0, 0)
  point P1 (32.12, 20.4855)
  point P2 (10.5, 23.6845)
  point P3 (-10.5, 23.6845)
  constraints: 8 end point, 3 collinear, 2 point on circle, 1 parallel
extrude "Extrusión21" add sketch "Boceto21" against normal blind 15 contours A0 L10 A6 L12 | A12 L6 A6 L8
sketch "Boceto22" plane through (0, 0, 40) normal (0, 0, -1) x (-1, 0, 0)
  arc A0 (50.4651, 6.5476) -> (61.1056, 0) centre (80, 42.625) ccw projected
  line L0 (49.1982, 5) -> (50.4651, 6.5476) projected
  arc A1 (49.1982, 5) -> (56.6013, 0) centre (80, 42.625) ccw projected
  line L1 (61.1056, 0) -> (56.6013, 0) projected
  arc A2 (-61.1056, 0) -> (-50.4651, 6.5476) centre (-80, 42.625) ccw projected
  line L2 (-56.6013, 0) -> (-61.1056, 0) projected
  arc A3 (-56.6013, 0) -> (-49.1982, 5) centre (-80, 42.625) ccw projected
  line L3 (-50.4651, 6.5476) -> (-49.1982, 5) projected
  point P0 (0, 0)
extrude "Extrusión22" add sketch "Boceto22" along normal up to surface (20 mm away)
ref_plane "Plano de trabajo2" through (0, 0, -85) normal (0, 0, 1) x (1, 0, 0)
mirror "Simetría4" about plane through (0, 0, -85) normal (0, 0, 1) of "Extrusión19", "Extrusión20", "Extrusión21", "Extrusión22"
fillet "Empalme1" radius 1.5 4 edges at (-21.8128, 26.4681, 95) (21.8128, 26.4681, 95) (-21.8128, 26.4681, -265) (21.8128, 26.4681, -265)
equation "\"d43\" = d42"
equation "\"d47\" = d46"
equation "\"d48\" = d46"
equation "\"d50\" = d49"
equation "\"d3\" = d2"
